Autodesk Fusion 360 part; units mm, degrees
(part 2 of 2)
equation "d30 = L1a_FirstNotch + NotchWidth / 2"
equation "d31 = LogDia / 2 + 1 mm"
equation "d32 = LogDia"
equation "d34 = max(L1a_Notches; 2)"
equation "d36 = L1a_NotchStep"
equation "L1b_Length = 1.5 in" comment "Overall length"
equation "L1b_Notches = 1" comment "Number of notch positions"
equation "L1b_FirstNotch = ( L1b_Length - ( L1b_Notches - 1 ) * NotchCenters ) / 2" comment "Centre of the first notch (keeps the row of notches centred)"
equation "L1b_NotchStep = NotchCenters * min(1; L1b_Notches - 1) + 0.001 mm * ( 1 - min(1; L1b_Notches - 1) )" comment "Pattern step: NotchCenters, or about zero when there is only one notch"
equation "d42 = LogDia / 2 - PrintFlat"
equation "d43 = LogDia"
equation "d44 = L1b_Length"
equation "d46 = L1b_FirstNotch - NotchWidth / 2"
equation "d47 = LogDia / 2 - NotchDepth"
equation "d48 = L1b_FirstNotch + NotchWidth / 2"
equation "d49 = LogDia / 2 + 1 mm"
equation "d50 = L1b_FirstNotch - NotchWidth / 2"
equation "d51 = LogDia / 2 - NotchDepth"
equation "d52 = L1b_FirstNotch + NotchWidth / 2"
equation "d53 = LogDia / 2 + 1 mm"
equation "d54 = LogDia"
equation "d56 = max(L1b_Notches; 2)"
equation "d58 = L1b_NotchStep"
equation "L1oct_Length = 1.5 in" comment "Overall length"
equation "L1oct_Notches = 1" comment "Number of notch positions"
equation "L1oct_FirstNotch = ( L1oct_Length - ( L1oct_Notches - 1 ) * NotchCenters ) / 2" comment "Centre of the first notch (keeps the row of notches centred)"
equation "L1oct_NotchStep = NotchCenters * min(1; L1oct_Notches - 1) + 0.001 mm * ( 1 - min(1; L1oct_Notches - 1) )" comment "Pattern step: NotchCenters, or about zero when there is only one notch"
equation "d64 = LogDia / 2"
equation "d65 = LogDia / 2"
equation "d66 = LogDia"
equation "d67 = L1oct_Length"
equation "d69 = LogDia * ( 1 - sqrt(2) / 2 )"
equation "d70 = L1oct_FirstNotch - NotchWidth / 2"
equation "d71 = LogDia / 2 - NotchDepth"
equation "d72 = L1oct_FirstNotch + NotchWidth / 2"
equation "d73 = LogDia / 2 + 1 mm"
equation "d74 = L1oct_FirstNotch - NotchWidth / 2"
equation "d75 = LogDia / 2 - NotchDepth"
equation "d76 = L1oct_FirstNotch + NotchWidth / 2"
equation "d77 = LogDia / 2 + 1 mm"
equation "d78 = LogDia"
equation "d80 = max(L1oct_Notches; 2)"
equation "d82 = L1oct_NotchStep"
equation "L2a_Length = 4.5 in" comment "Overall length"
equation "L2a_Notches = 2" comment "Number of notch positions"
equation "L2a_FirstNotch = ( L2a_Length - ( L2a_Notches - 1 ) * NotchCenters ) / 2" comment "Centre of the first notch (keeps the row of notches centred)"
equation "L2a_NotchStep = NotchCenters * min(1; L2a_Notches - 1) + 0.001 mm * ( 1 - min(1; L2a_Notches - 1) )" comment "Pattern step: NotchCenters, or about zero when there is only one notch"
equation "d88 = LogDia / 2 - PrintFlat"
equation "d89 = LogDia"
equation "d90 = L2a_Length"
equation "d92 = L2a_FirstNotch - NotchWidth / 2"
equation "d93 = LogDia / 2 - NotchDepth"
equation "d94 = L2a_FirstNotch + NotchWidth / 2"
equation "d95 = LogDia / 2 + 1 mm"
equation "d96 = L2a_FirstNotch - NotchWidth / 2"
equation "d97 = LogDia / 2 - NotchDepth"
equation "d98 = L2a_FirstNotch + NotchWidth / 2"
equation "d99 = LogDia / 2 + 1 mm"
equation "d100 = LogDia"
equation "d102 = max(L2a_Notches; 2)"
equation "d104 = L2a_NotchStep"
equation "L2b_Length = 6 in" comment "Overall length"
equation "L2b_Notches = 2" comment "Number of notch positions"
equation "L2b_FirstNotch = ( L2b_Length - ( L2b_Notches - 1 ) * NotchCenters ) / 2" comment "Centre of the first notch (keeps the row of notches centred)"
equation "L2b_NotchStep = NotchCenters * min(1; L2b_Notches - 1) + 0.001 mm * ( 1 - min(1; L2b_Notches - 1) )" comment "Pattern step: NotchCenters, or about zero when there is only one notch"
equation "d110 = LogDia / 2 - PrintFlat"
equation "d111 = LogDia"
equation "d112 = L2b_Length"
equation "d114 = L2b_FirstNotch - NotchWidth / 2"
equation "d115 = LogDia / 2 - NotchDepth"
equation "d116 = L2b_FirstNotch + NotchWidth / 2"
equation "d117 = LogDia / 2 + 1 mm"
equation "d118 = L2b_FirstNotch - NotchWidth / 2"
equation "d119 = LogDia / 2 - NotchDepth"
equation "d120 = L2b_FirstNotch + NotchWidth / 2"
equation "d121 = LogDia / 2 + 1 mm"
equation "d122 = LogDia"
equation "d124 = max(L2b_Notches; 2)"
equation "d126 = L2b_NotchStep"
equation "L3_Length = 7.625 in" comment "Overall length"
equation "L3_Notches = 3" comment "Number of notch positions"
equation "L3_FirstNotch = ( L3_Length - ( L3_Notches - 1 ) * NotchCenters ) / 2" comment "Centre of the first notch (keeps the row of notches centred)"
equation "L3_NotchStep = NotchCenters * min(1; L3_Notches - 1) + 0.001 mm * ( 1 - min(1; L3_Notches - 1) )" comment "Pattern step: NotchCenters, or about zero when there is only one notch"
equation "d132 = LogDia / 2 - PrintFlat"
equation "d133 = LogDia"
equation "d134 = L3_Length"
equation "d136 = L3_FirstNotch - NotchWidth / 2"
equation "d137 = LogDia / 2 - NotchDepth"
equation "d138 = L3_FirstNotch + NotchWidth / 2"
equation "d139 = LogDia / 2 + 1 mm"
equation "d140 = L3_FirstNotch - NotchWidth / 2"
equation "d141 = LogDia / 2 - NotchDepth"
equation "d142 = L3_FirstNotch + NotchWidth / 2"
equation "d143 = LogDia / 2 + 1 mm"
equation "d144 = LogDia"
equation "d146 = max(L3_Notches; 2)"
equation "d148 = L3_NotchStep"
equation "L4_Length = 10.625 in" comment "Overall length"
equation "L4_Notches = 4" comment "Number of notch positions"
equation "L4_FirstNotch = ( L4_Length - ( L4_Notches - 1 ) * NotchCenters ) / 2" comment "Centre of the first notch (keeps the row of notches centred)"
equation "L4_NotchStep = NotchCenters * min(1; L4_Notches - 1) + 0.001 mm * ( 1 - min(1; L4_Notches - 1) )" comment "Pattern step: NotchCenters, or about zero when there is only one notch"
equation "d154 = LogDia / 2 - PrintFlat"
equation "d155 = LogDia"
equation "d156 = L4_Length"
equation "d158 = L4_FirstNotch - NotchWidth / 2"
equation "d159 = LogDia / 2 - NotchDepth"
equation "d160 = L4_FirstNotch + NotchWidth / 2"
equation "d161 = LogDia / 2 + 1 mm"
equation "d162 = L4_FirstNotch - NotchWidth / 2"
equation "d163 = LogDia / 2 - NotchDepth"
equation "d164 = L4_FirstNotch + NotchWidth / 2"
equation "d165 = LogDia / 2 + 1 mm"
equation "d166 = LogDia"
equation "d168 = max(L4_Notches; 2)"
equation "d170 = L4_NotchStep"
equation "BevLong_Length = 4.75 in" comment "Overall length"
equation "BevLong_Notches = 2" comment "Number of notch positions"
equation "BevLong_FirstNotch = ( BevLong_Length - ( BevLong_Notches - 1 ) * NotchCenters ) / 2" comment "Centre of the first notch (keeps the row of notches centred)"
equation "BevLong_NotchStep = NotchCenters * min(1; BevLong_Notches - 1) + 0.001 mm * ( 1 - min(1; BevLong_Notches - 1) )" comment "Pattern step: NotchCenters, or about zero when there is only one notch"
equation "d176 = LogDia / 2 - PrintFlat"
equation "d177 = LogDia"
equation "BevLong_EndRadius = 4 mm" comment "Radius of the rounded ends"
equation "d179 = BevLong_Length"
equation "d182 = BevLong_EndRadius"
equation "d183 = BevLong_Length"
equation "d185 = BevLong_FirstNotch - NotchWidth / 2"
equation "d186 = LogDia / 2 - NotchDepth"
equation "d187 = BevLong_FirstNotch + NotchWidth / 2"
equation "d188 = LogDia / 2 + 1 mm"
equation "d189 = BevLong_FirstNotch - NotchWidth / 2"
equation "d190 = LogDia / 2 - NotchDepth"
equation "d191 = BevLong_FirstNotch + NotchWidth / 2"
equation "d192 = LogDia / 2 + 1 mm"
equation "d193 = LogDia"
equation "d195 = max(BevLong_Notches; 2)"
equation "d197 = BevLong_NotchStep"
equation "Half2_Length = 4.5 in" comment "Overall length"
equation "Half2_Notches = 2" comment "Number of notch positions"
equation "Half2_FirstNotch = ( Half2_Length - ( Half2_Notches - 1 ) * NotchCenters ) / 2" comment "Centre of the first notch (keeps the row of notches centred)"
equation "Half2_NotchStep = NotchCenters * min(1; Half2_Notches - 1) + 0.001 mm * ( 1 - min(1; Half2_Notches - 1) )" comment "Pattern step: NotchCenters, or about zero when there is only one notch"
equation "d203 = HalfLogHeight - LogDia / 2"
equation "d204 = LogDia"
equation "d205 = Half2_Length"
equation "d207 = Half2_FirstNotch - NotchWidth / 2"
equation "d208 = HalfLogHeight - NotchDepth"
equation "d209 = Half2_FirstNotch + NotchWidth / 2"
equation "d210 = HalfLogHeight + 1 mm"
equation "d211 = LogDia + 2 mm"
equation "d213 = max(Half2_Notches; 2)"
equation "d215 = Half2_NotchStep"
equation "Half3_Length = 7.5 in" comment "Overall length"
equation "Half3_Notches = 3" comment "Number of notch positions"
equation "Half3_FirstNotch = ( Half3_Length - ( Half3_Notches - 1 ) * NotchCenters ) / 2" comment "Centre of the first notch (keeps the row of notches centred)"
equation "Half3_NotchStep = NotchCenters * min(1; Half3_Notches - 1) + 0.001 mm * ( 1 - min(1; Half3_Notches - 1) )" comment "Pattern step: NotchCenters, or about zero when there is only one notch"
equation "d221 = HalfLogHeight - LogDia / 2"
equation "d222 = LogDia"
equation "d223 = Half3_Length"
equation "d225 = Half3_FirstNotch - NotchWidth / 2"
equation "d226 = HalfLogHeight - NotchDepth"
equation "d227 = Half3_FirstNotch + NotchWidth / 2"
equation "d228 = HalfLogHeight + 1 mm"
equation "d229 = LogDia + 2 mm"
equation "d231 = max(Half3_Notches; 2)"
equation "d233 = Half3_NotchStep"
equation "BevShort_Length = 1.5 in" comment "Length along the long edge"
equation "BevShort_Angle = 39 deg" comment "Angle of the slanted end (roof pitch of the wooden triangle)"
equation "d237 = LogDia / 2 - PrintFlat"
equation "d238 = LogDia"
equation "d239 = BevShort_Length"
equation "d241 = BevShort_Length"
equation "d242 = LogDia / 2"
equation "d243 = LogDia / 2"
equation "d244 = BevShort_Length - LogDia / tan(BevShort_Angle)"
equation "d245 = LogDia"
equation "Solid1_Length = 1.375 in" comment "Length"
equation "d248 = LogDia"
equation "d249 = Solid1_Length"
equation "Solid2_Length = 1.625 in" comment "Length"
equation "d252 = LogDia"
equation "d253 = Solid2_Length"
equation "GableL_Width = 8.5 in" comment "Overall width"
equation "GableL_Notches = 3" comment "Number of notch positions"
equation "GableL_FirstNotch = ( GableL_Width - ( GableL_Notches - 1 ) * NotchCenters ) / 2" comment "Centre of the first notch (keeps the row of notches centred)"
equation "GableL_NotchStep = NotchCenters * min(1; GableL_Notches - 1) + 0.001 mm * ( 1 - min(1; GableL_Notches - 1) )" comment "Pattern step: NotchCenters, or about zero when there is only one notch"
equation "GableL_Steps = 7" comment "Roof steps per side"
equation "GableL_EaveHeight = 7.5 mm" comment "Height of the slope start above the base"
equation "GableL_LipThk = 5.4 mm" comment "Eave lip thickness"
equation "GableL_LipHeight = 3.6 mm" comment "Eave lip height above the slope start"
equation "GableL_Riser = 2.9 mm" comment "Vertical riser of each roof step"
equation "GableL_Height = 2.25 in" comment "Overall height at the peak"
equation "GableL_StepRun = ( GableL_Width / 2 - GableL_LipThk ) / GableL_Steps" comment "Horizontal run of one step"
equation "GableL_TreadRise = ( GableL_Height - GableL_EaveHeight - ( GableL_Steps - 1 ) * GableL_Riser ) / GableL_Steps" comment "Rise of one sloped tread"
equation "GableL_StepPitch = sqrt(GableL_StepRun ^ 2 + ( GableL_TreadRise + GableL_Riser ) ^ 2)" comment "Step spacing measured along the slope"
equation "PlasticRoofAngle = atan(( GableL_Height + GableL_Riser - GableL_EaveHeight ) / ( GableL_Width / 2 - GableL_LipThk ))" comment "Pitch of the large plastic gable. The small gable and the chimney follow it"
equation "GableS_Width = 5.8 in" comment "Overall width"
equation "GableS_Notches = 2" comment "Number of notch positions"
equation "GableS_FirstNotch = ( GableS_Width - ( GableS_Notches - 1 ) * NotchCenters ) / 2" comment "Centre of the first notch (keeps the row of notches centred)"
equation "GableS_NotchStep = NotchCenters * min(1; GableS_Notches - 1) + 0.001 mm * ( 1 - min(1; GableS_Notches - 1) )" comment "Pattern step: NotchCenters, or about zero when there is only one notch"
equation "GableS_Steps = 5" comment "Roof steps per side"
equation "GableS_EaveHeight = 7.5 mm" comment "Height of the slope start above the base"
equation "GableS_LipThk = 5.4 mm" comment "Eave lip thickness"
equation "GableS_LipHeight = 3.6 mm" comment "Eave lip height above the slope start"
equation "GableS_Riser = 2.9 mm" comment "Vertical riser of each roof step"
equation "GableS_Height = GableS_EaveHeight + tan(PlasticRoofAngle) * ( GableS_Width / 2 - GableS_LipThk ) - GableS_Riser" comment "Overall height at the peak"
equation "GableS_StepRun = ( GableS_Width / 2 - GableS_LipThk ) / GableS_Steps" comment "Horizontal run of one step"
equation "GableS_TreadRise = ( GableS_Height - GableS_EaveHeight - ( GableS_Steps - 1 ) * GableS_Riser ) / GableS_Steps" comment "Rise of one sloped tread"
equation "GableS_StepPitch = sqrt(GableS_StepRun ^ 2 + ( GableS_TreadRise + GableS_Riser ) ^ 2)" comment "Step spacing measured along the slope"
equation "d282 = GableL_Width / 2"
equation "d283 = GableL_Height + GableL_Riser"
equation "d284 = GableL_LipThk"
equation "d285 = GableL_EaveHeight"
equation "d286 = GableL_EaveHeight + GableL_LipHeight"
equation "d287 = GableThk"
equation "d289 = GableL_LipThk"
equation "d290 = GableL_EaveHeight"
equation "d291 = GableL_LipThk + GableL_StepRun"
equation "d292 = GableL_EaveHeight + GableL_TreadRise + GableL_Riser"
equation "d293 = GableL_EaveHeight + GableL_TreadRise"
equation "d294 = GableThk"
equation "d296 = GableL_Steps"
equation "d298 = GableL_StepPitch"
equation "d300 = GableL_Width / 2"
equation "d304 = GableL_FirstNotch - NotchWidth / 2"
equation "d306 = GableL_FirstNotch + NotchWidth / 2"
equation "d307 = NotchDepth"
equation "d308 = GableThk"
equation "d310 = max(GableL_Notches; 2)"
equation "d312 = GableL_NotchStep"
equation "d314 = GableS_Width / 2"
equation "d315 = GableS_Height + GableS_Riser"
equation "d316 = GableS_LipThk"
equation "d317 = GableS_EaveHeight"
equation "d318 = GableS_EaveHeight + GableS_LipHeight"
equation "d319 = GableThk"
equation "d321 = GableS_LipThk"
equation "d322 = GableS_EaveHeight"
equation "d323 = GableS_LipThk + GableS_StepRun"
equation "d324 = GableS_EaveHeight + GableS_TreadRise + GableS_Riser"
equation "d325 = GableS_EaveHeight + GableS_TreadRise"
equation "d326 = GableThk"
equation "d328 = GableS_Steps"
equation "d330 = GableS_StepPitch"
equation "d332 = GableS_Width / 2"
equation "d336 = GableS_FirstNotch - NotchWidth / 2"
equation "d338 = GableS_FirstNotch + NotchWidth / 2"
equation "d339 = NotchDepth"
equation "d340 = GableThk"
equation "d342 = max(GableS_Notches; 2)"
equation "d344 = GableS_NotchStep"
equation "GableTri_Width = 4.875 in" comment "Overall width"
equation "GableTri_Notches = 2" comment "Number of notch positions"
equation "GableTri_FirstNotch = ( GableTri_Width - ( GableTri_Notches - 1 ) * NotchCenters ) / 2" comment "Centre of the first notch (keeps the row of notches centred)"
equation "GableTri_NotchStep = NotchCenters * min(1; GableTri_Notches - 1) + 0.001 mm * ( 1 - min(1; GableTri_Notches - 1) )" comment "Pattern step: NotchCenters, or about zero when there is only one notch"
equation "GableTri_Height = 2 in" comment "Height at the peak"
equation "d351 = GableTri_Width"
equation "d352 = GableTri_Width / 2"
equation "d353 = GableTri_Height"
equation "d354 = GableThk"
equation "d356 = GableTri_FirstNotch - NotchWidth / 2"
equation "d358 = GableTri_FirstNotch + NotchWidth / 2"
equation "d359 = NotchDepth"
equation "d360 = GableThk"
equation "d362 = max(GableTri_Notches; 2)"
equation "d364 = GableTri_NotchStep"
equation "ShFlat6_Length = 6 in" comment "Length"
equation "d367 = FlatShingleWidth / 2"
equation "d368 = ShFlat6_Length"
equation "d369 = FlatShingleWidth / 2"
equation "d370 = ShingleThk"
equation "ShFlat9_Length = 9 in" comment "Length"
equation "d373 = FlatShingleWidth / 2"
equation "d374 = ShFlat9_Length"
equation "d375 = FlatShingleWidth / 2"
equation "d376 = ShingleThk"
equation "ShFlat11_Length = 11 in" comment "Length"
equation "d379 = FlatShingleWidth / 2"
equation "d380 = ShFlat11_Length"
equation "d381 = FlatShingleWidth / 2"
equation "d382 = ShingleThk"
equation "ShRidge5_Length = 5.625 in" comment "Length"
equation "d385 = RidgeShingleWidth / 2"
equation "d386 = ShRidge5_Length"
equation "d387 = RidgeShingleWidth / 2"
equation "d388 = ShingleThk"
equation "d390 = RidgeGrooveWidth / 2"
equation "d391 = ShingleThk"
equation "d392 = RidgeGrooveWidth / 2"
equation "d393 = ShingleThk - RidgeGrooveDepth"
equation "d394 = ShRidge5_Length"
equation "ShRidge6_Length = 6 in" comment "Length"
equation "d397 = RidgeShingleWidth / 2"
equation "d398 = ShRidge6_Length"
equation "d399 = RidgeShingleWidth / 2"
equation "d400 = ShingleThk"
equation "d402 = RidgeGrooveWidth / 2"
equation "d403 = ShingleThk"
equation "d404 = RidgeGrooveWidth / 2"
equation "d405 = ShingleThk - RidgeGrooveDepth"
equation "d406 = ShRidge6_Length"
equation "ShRidge9_Length = 9 in" comment "Length"
equation "d409 = RidgeShingleWidth / 2"
equation "d410 = ShRidge9_Length"
equation "d411 = RidgeShingleWidth / 2"
equation "d412 = ShingleThk"
equation "d414 = RidgeGrooveWidth / 2"
equation "d415 = ShingleThk"
equation "d416 = RidgeGrooveWidth / 2"
equation "d417 = ShingleThk - RidgeGrooveDepth"
equation "d418 = ShRidge9_Length"
equation "Chimney_Width = 1.375 in" comment "Width across the ridge"
equation "Chimney_Depth = 1 in" comment "Depth along the ridge"
equation "Chimney_Height = 1.2 in" comment "Overall height"
equation "Chimney_Wall = 0.12 in" comment "Wall thickness of the open top"
equation "Chimney_Pocket = 0.5 in" comment "Depth of the open top"
equation "Chimney_VDepth = Chimney_Width / 2 * tan(PlasticRoofAngle)" comment "Depth of the V cut that straddles the ridge"
equation "d426 = Chimney_Width / 2"
equation "d427 = Chimney_Depth / 2"
equation "d428 = Chimney_Width / 2"
equation "d429 = Chimney_Depth / 2"
equation "d430 = Chimney_Height"
equation "d432 = Chimney_Width / 2 - Chimney_Wall"
equation "d433 = Chimney_Depth / 2 - Chimney_Wall"
equation "d434 = Chimney_Width / 2 - Chimney_Wall"
equation "d435 = Chimney_Depth / 2 - Chimney_Wall"
equation "d436 = Chimney_Pocket"
equation "d438 = Chimney_Width / 2"
equation "d439 = Chimney_Height"
equation "d440 = Chimney_Width / 2"
equation "d441 = Chimney_Height - Chimney_VDepth"
equation "d442 = Chimney_Depth + 2 mm"
equation "Door_Courses = 4" comment "Log courses the panel spans"
equation "Door_Width = NotchCenters - LogDia - 2 * Clearance" comment "Width (fits the gap between crossing logs)"
equation "Door_Height = ( Door_Courses - 1 ) * CourseRise + LogDia - 2 * Clearance" comment "Height"
equation "d447 = Door_Width / 2"
equation "d448 = Door_Height / 2"
equation "d449 = Door_Width / 2"
equation "d450 = Door_Height / 2"
equation "d451 = PanelThk"
equation "Window_Courses = 3" comment "Log courses the panel spans"
equation "Window_Width = NotchCenters - LogDia - 2 * Clearance" comment "Width (fits the gap between crossing logs)"
equation "Window_Height = ( Window_Courses - 1 ) * CourseRise + LogDia - 2 * Clearance" comment "Height"
equation "Window_OpeningWidth = 1.125 in" comment "Opening width"
equation "Window_OpeningHeight = 0.625 in" comment "Opening height"
equation "d458 = Window_Width / 2"
equation "d459 = Window_Height / 2"
equation "d460 = Window_Width / 2"
equation "d461 = Window_Height / 2"
equation "d462 = Window_OpeningWidth / 2"
equation "d463 = Window_OpeningHeight / 2"
equation "d464 = Window_OpeningWidth / 2"
equation "d465 = Window_OpeningHeight / 2"
equation "d466 = PanelThk"
named bodies: "log_1insert_1-5_8", "log_1insert_1-1_2_round", "log_1insert_1-1_2_octagonal", "log_2insert_4-1_2", "log_2insert_6", "log_3insert_7-5_8", "log_4insert_10-5_8", "beveled_end_4-3_4", "half_log_4-1_2", "half_log_7-1_2", "beveled_end_1-1_2", "solid_log_1-3_8", "solid_log_1-5_8", "gable_plastic_8-1_2", "gable_plastic_small_2notch", "gable_wood_triangle_4x2", "shingle_flat_6", "shingle_flat_9", "shingle_flat_11", "shingle_ridge_5-5_8", "shingle_ridge_6", "shingle_ridge_9", "chimney", "extra_door", "extra_window"
